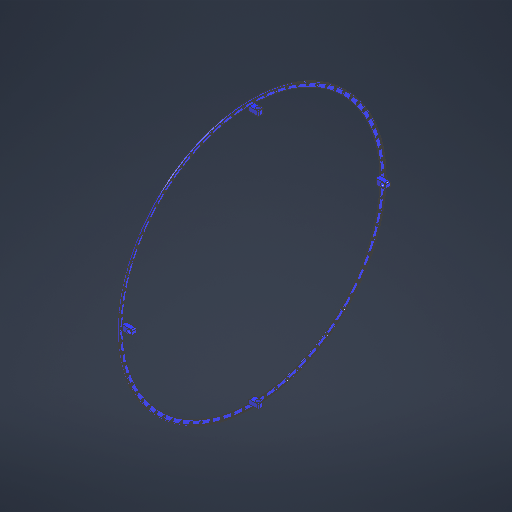
# Autodesk Inventor part: Cascet
Saved by Autodesk Inventor 2027.1 (Build 311270010, 270A)
## iProperties
Created: 2026-11-02
Part Number: Cascet
Material: Ogólny
Document SubType Name: Modeling
Designer: User
Density: 1 g/cm^3
Appearance: Domyślna
Mass: 1.31924 g
Surface Area: 58.6117 cm^2
Volume: 1.31924 cm^3
Author: User
Autodesk Inventor part; units mm, degrees
ref_plane "YZ Plane" through (0, 0, 0) normal (1, 0, 0) x (0, 1, 0)
ref_plane "XZ Plane" through (0, 0, 0) normal (0, 1, 0) x (-1, 0, 0)
ref_plane "XY Plane" through (0, 0, 0) normal (0, 0, 1) x (1, 0, 0)
sketch "Szkic1" plane through (0, 0, 0) normal (0, 1, 0) x (-1, 0, 0)
  line L0 (0, 0) -> (0, 118)
  line L1 (0, 0) -> (118, 0) construction
  line L2 (0, 0) -> (-30, 0) construction
  line L3 (0, 0) -> (30, 0) construction
  line L4 (-30, 0) -> (-30, 118) construction
  line L5 (-30, 118) -> (1, 118) construction
  circle A0 centre (1, 118) radius 1.45
  line L6 (0, 0) -> (0, 120)
  line L7 (0, 0) -> (120, 0) construction
  line L8 (1, 118) -> (0, 118) construction
  line L9 (1, 118) -> (0.6, 118) construction
  line L10 (1, 118) -> (1.4, 118) construction
  line L11 (1.4, 118) -> (1.4, 120) construction
  line L12 (1.4, 118) -> (3.4, 118) construction
  line L13 (1.4, 120) -> (1.4, 116) construction
  line L14 (0, 120) -> (1.4, 120)
  line L15 (1.4, 120) -> (1.4, 116)
  line L16 (1.4, 116) -> (0, 116)
  line L17 (0, 116) -> (0, 120)
  line L18 (1.4769, 118) -> (-0.45, 118)
  line L19 (1.4769, 118) -> (2.45, 118)
  line L20 (0.7, 116) -> (0.7, 120)
  line L21 (0.7, 116) -> (3.0738, 116) construction
  line L22 (0.7, 116) -> (-4.3, 116)
  line L23 (0.7, 116) -> (5.7, 116) construction
  line L24 (-4.3, 116) -> (-8.3, 116)
  line L25 (-4.3, 116) -> (-0.3, 116) construction
  line L26 (1.4, 116) -> (-7.6, 116)
  line L27 (-7.6, 116) -> (-7.6, 112)
  line L28 (-7.6, 112) -> (1.4, 112)
  line L29 (1.4, 112) -> (1.4, 116)
  line L30 (0.7, 120) -> (0.7, 119.3)
  line L31 (0.7, 119.3) -> (0, 119.3)
  point P0 (1.44, 108.5)
  point P1 (0, 119.05)
  point P2 (0, 116.95)
  point P3 (0.7, 119.4186)
  dimension "d0" = 118
  dimension "d1" = 90
  dimension "d2" = 30
  dimension "d3" = 180
  dimension "d4" = 90
  dimension "d5" = 31
  dimension "d6" = 2.9
  dimension "d7" = 120
  dimension "d8" = 90
  dimension "d12" = 2
  dimension "d13" = 90
  dimension "d84" = 4
  dimension "d86" = 5
  dimension "d87" = 180
  dimension "d89" = 180
  dimension "d90" = 9
  dimension "d91" = 4
  dimension "d102" = -0.7
  dimension "d103" = 0.7
  constraints: 64 end point, 12 horizontal, 7 equal length, 7 perpendicular, 6 point on line, 4 parallel, 2 collinear, 2 midpoint, 2 point on circle, 2 vertical, 1 centre point, 1 coincident
  measures "d0" distance of L0.start L0.end
  measures "d1" angle of L1 L0
  measures "d2" distance of L0.start L2.end
  measures "d3" angle of L2 L3
  measures "d4" angle of L2 L4
  measures "d5" distance of L4.end L5.end
  measures "d6" diameter of A0
  measures "d7" distance of L0.start L6.end
  measures "d8" angle of L7 L6
  measures "d12" distance of L10.end L11.end
  measures "d13" angle of L12 L11
  measures "d84" distance from line of L20.end L16
  measures "d86" distance of L20.start L22.end
  measures "d87" angle of L22 L23
  measures "d89" angle of L24 L25
  measures "d90" distance of L28.end L27.end
  measures "d91" distance of L27.end L26.end
  measures "d102" distance between parallel lines of L29 L20
  measures "d103" distance of L20.end L30.end
revolve "Obrót1" add sketch "Szkic1" angle 360 about axis through (0, 0, 0) along (1, 0, 0) contours L20 A0 L15 L16 | L20 L18 L15 A0 | L20 A0 L15 L18 | L31 L6 L14 L20 A0 | A0 L20 L31 | A0 L20 L14 L15
revolve "Obrót2" cut sketch "Szkic1" angle 360 about axis through (-1, 0, 118) along (1, 0, 0) picked at (1.0897, 117.52) picked at (1.4961, 117.11) contours A0 L18 L0 | L0 L18 L20 A0 | L20 L18 L15 A0 | L15 L18 L19 A0
pattern_circular "Szyk kołowy1" count 75 over 360 about axis through (-10, 0, 0) along (1, 0, 0) of "Obrót2"
extrude "Wyciągnięcie proste5" add sketch "Szkic1" along normal mid plane 5 contours L28 L27 L24 L22 L0 | L0 L16 L29 L28
sketch "Szkic7" plane through (-0.7, -2.5, 116) normal (0, 0, 1) x (1, 0, 0)
  line L0 (0.7, 2.5) -> (5.7, 2.5)
  line L1 (8.3, 5) -> (-0.7, 5) projected
  line L2 (0.7, 2.5) -> (5.7, 2.5) construction
  circle A0 centre (5.7, 2.5) radius 2
  dimension "d94" = 5
  dimension "d95" = 0
  dimension "d96" = 4
  constraints: 4 end point, 1 centre point, 1 coincident, 1 collinear, 1 horizontal, 1 parallel
  measures "d94" distance of L0.start L0.end
  measures "d95" distance between parallel lines of L0 L2
  measures "d96" diameter of A0
extrude "Wyciągnięcie proste6" cut sketch "Szkic7" against normal blind 7.25
pattern_circular "Szyk kołowy4" count 4 over 360 about axis through (-10, 0, 0) along (1, 0, 0) of "Wyciągnięcie proste6", "Wyciągnięcie proste5"
fillet "Zaokrąglenie8" radius 1 1 edges at (-1.4, 0, -112)
fillet "Zaokrąglenie9" radius 1 2 edges at (7.6, -2.5, -114) (7.6, 2.5, -114)
pattern_circular "Szyk kołowy5" count 4 over 360 about axis through (-10, 0, 0) along (1, 0, 0) of "Zaokrąglenie9", "Zaokrąglenie8"
equation "\"d0\" = Base_radius - 0.5 * Base_wall_thickness"
equation "\"d2\" = Base_height"
equation "\"d7\" = Base_radius"
equation "\"Base_radius\" = 120"
equation "\"Base_wall_thickness\" = 4"
equation "\"Base_height\" = 30"
